P_B1_saved (Autodesk Fusion 360 design; units mm, degrees)
part number: 2026-11-12-11-47-49-209
Autodesk Fusion 360 part; units mm, degrees
sketch "Sketch1" plane through (0, 0, 0) normal (0, 0, 1) x (1, 0, 0)
  line L0 (0, 0) -> (8, 0)
  line L1 (8, 0) -> (8, 8)
  line L2 (8, 8) -> (0, 8)
  line L3 (0, 8) -> (0, 0)
extrude "Extrude1" add sketch "Sketch1" along normal blind 12
equation "heightB = 12 mm" comment "Kit link control height"
equation "d2 = heightB"
named bodies: "KitLinkPartBBody"
